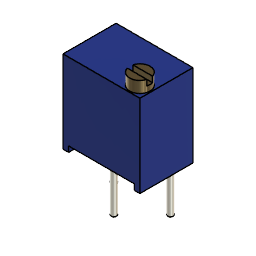
JBR-3266W (Autodesk Fusion 360 design; units mm, degrees)
part number: 2026-02-03-21-40-09-572
Autodesk Fusion 360 part; units mm, degrees
sketch "Sketch1" plane through (0, 0, 0) normal (0, 0, 1) x (1, 0, 0)
  line L0 (3.4, 2.35) -> (-3.4, 2.35)
  line L1 (-3.4, 2.35) -> (-3.4, -2.35)
  line L2 (-3.4, -2.35) -> (3.4, -2.35)
  line L3 (3.4, -2.35) -> (3.4, 2.35)
  line L4 (3.4, 2.35) -> (-3.4, -2.35) construction
  line L5 (-3.4, 2.35) -> (3.4, -2.35) construction
  dimension "d1" = 6.8
  dimension "d2" = 4.7
  constraint horizontal L0
  constraint perpendicular L0 L1
  constraint parallel L0 L2
  constraint parallel L1 L3
  constraint coincident L4 origin
  constraint coincident L5 origin
  measures "d1" distance of L1.end L2.end
  measures "d2" distance of L0.end L1.end
extrude "Extrude1" add sketch "Sketch1" along normal blind 7.3 makes body 1
sketch "Sketch2" plane through (0, -2.35, 0) normal (0, -1, 0) x (1, 0, 0)
  line L0 (-3.4, 0) -> (3.4, 0)
  line L1 (3.4, 0) -> (3.4, 7.3)
  line L2 (3.4, 7.3) -> (-3.4, 7.3)
  line L3 (-3.4, 7.3) -> (-3.4, 0)
  line L4 (2.9, 0.5) -> (-2.9, 0.5)
  line L5 (-2.9, 0.5) -> (-2.9, -0.5)
  line L6 (-2.9, -0.5) -> (2.9, -0.5)
  line L7 (2.9, -0.5) -> (2.9, 0.5)
  line L8 (2.9, 0.5) -> (-2.9, -0.5) construction
  line L9 (-2.9, 0.5) -> (2.9, -0.5) construction
  dimension "d5" = 5.8
  dimension "d6" = 1
  constraint horizontal L4
  constraint perpendicular L4 L5
  constraint parallel L4 L6
  constraint parallel L5 L7
  constraint coincident L8 origin
  constraint coincident L9 origin
  measures "d5" distance of L5.end L6.end
  measures "d6" distance of L4.end L5.end
extrude "Extrude2" cut sketch "Sketch2" against normal blind 4.7 contours L0 L4 L5 L7 bodies 1
sketch "Sketch3" plane through (0, 0, 7.3) normal (0, 0, 1) x (-1, 0, 0)
  line L0 (-3.4, 2.35) -> (-3.4, -2.35)
  line L1 (-3.4, -2.35) -> (3.4, -2.35)
  line L2 (3.4, -2.35) -> (3.4, 2.35)
  line L3 (3.4, 2.35) -> (-3.4, 2.35)
  line L4 (-3.4, 2.35) -> (-2.4, 2.35) construction
  line L5 (-2.4, 2.35) -> (-2.4, 1.35) construction
  line L6 (-2.4, 1.35) -> (-3.4, 1.35) construction
  line L7 (-3.4, 1.35) -> (-3.4, 2.35) construction
  circle A0 centre (-2.4, 1.35) radius 0.9
  dimension "d9" = 1
  dimension "d10" = 1
  dimension "d11" = 1.8
  constraint horizontal L4
  constraint vertical L5
  constraint horizontal L6
  constraint vertical L7
  constraint coincident L0.start L3.end
  constraint coincident L5.end L6.start
  measures "d9" distance of L0.start L4.end
  measures "d10" distance of L0.start L6.end
  measures "d11" diameter of A0
extrude "Extrude3" add sketch "Sketch3" along normal blind 1 separate body contours A0 makes body 2
sketch "Sketch4" plane through (0, 0, 8.3) normal (0, 0, 1) x (-1, 0, 0)
  circle A0 centre (-2.4, 1.35) radius 0.9
  line L0 (-3.3, 1.1) -> (-1.5, 1.1)
  line L1 (-1.5, 1.1) -> (-1.5, 1.6)
  line L2 (-1.5, 1.6) -> (-3.3, 1.6)
  line L3 (-3.3, 1.6) -> (-3.3, 1.1)
  line L4 (-3.3, 1.1) -> (-1.5, 1.6) construction
  line L5 (-1.5, 1.1) -> (-3.3, 1.6) construction
  point P0 (-2.4, 1.35)
  dimension "d14" = 1.8
  dimension "d15" = 0.5
  constraint horizontal L0
  constraint perpendicular L0 L1
  constraint parallel L0 L2
  constraint parallel L1 L3
  constraint coincident L4 P0
  constraint coincident L5 P0
  constraint coincident P0 A0.centre
  measures "d14" distance of L1.end L2.end
  measures "d15" distance of L0.end L1.end
extrude "Extrude4" cut sketch "Sketch4" against normal blind 0.5 contours A0 L0 L2 bodies 2
sketch "Sketch5" plane through (0, 0, 0.5) normal (0, 0, -1) x (1, 0, 0)
  line L0 (2.9, 2.35) -> (-2.9, 2.35)
  line L1 (-2.9, 2.35) -> (-2.9, -2.35)
  line L2 (-2.9, -2.35) -> (2.9, -2.35)
  line L3 (2.9, -2.35) -> (2.9, 2.35)
  line L4 (2.5, 1.25) -> (-2.5, 1.25) construction
  line L5 (-2.5, 1.25) -> (-2.5, -1.25) construction
  line L6 (-2.5, -1.25) -> (2.5, -1.25) construction
  line L7 (2.5, -1.25) -> (2.5, 1.25) construction
  line L8 (2.5, 1.25) -> (-2.5, -1.25) construction
  line L9 (-2.5, 1.25) -> (2.5, -1.25) construction
  circle A0 centre (0, 1.25) radius 0.25
  circle A1 centre (-2.5, -1.25) radius 0.25
  circle A2 centre (2.5, -1.25) radius 0.25
  dimension "d20" = 5
  dimension "d21" = 2.5
  dimension "d22" = 0.5
  dimension "d23" = 0.5
  dimension "d24" = 0.5
  constraint horizontal L4
  constraint perpendicular L4 L5
  constraint parallel L4 L6
  constraint parallel L5 L7
  constraint coincident L8 origin
  constraint coincident L9 origin
  constraint midpoint L4 A0.centre
  constraint coincident L5.end L6.start
  constraint coincident L6.end L7.start
  measures "d20" distance of L5.end L6.end
  measures "d21" distance of L4.end L5.end
  measures "d22" diameter of A0
  measures "d23" diameter of A1
  measures "d24" diameter of A2
extrude "Extrude5" add sketch "Sketch5" along normal blind 4.5 separate body contours A0 | A1 | A2 makes body 3 at (-2.2503, 1.2625, -2.5) makes body 4 at (0.2497, -1.2375, -2.5) makes body 5 at (2.7497, 1.2625, -2.5)
fillet "Fillet1" radius 0.15 3 edges at (-2.7331, 1.3404, -4) (-0.2331, -1.1596, -4) (2.2669, 1.3404, -4) on bodies 3 4 5
